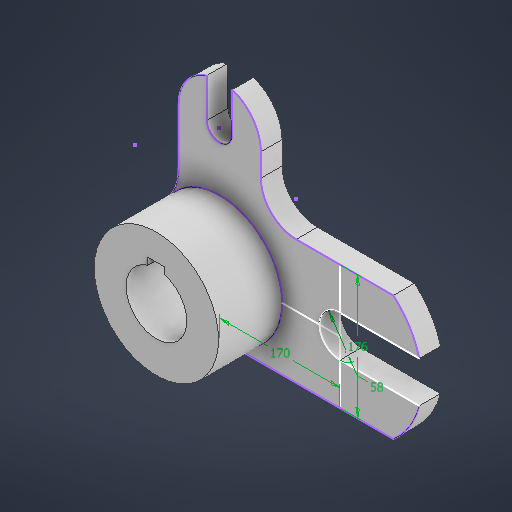
# Autodesk Inventor part: Peça3
Saved by Autodesk Inventor 2026.2 (Build 302298000, 298)
## iProperties
Created: 2026-07-31
Part Number: Peça3
Material: Genérico
Document SubType Name: Modeling
Designer: IFSP
Density: 1 g/cm^3
Appearance: Padrão
Author: IFSP
Autodesk Inventor part; units mm, degrees
ref_plane "YZ Plane" through (0, 0, 0) normal (1, 0, 0) x (0, 1, 0)
ref_plane "XZ Plane" through (0, 0, 0) normal (0, 1, 0) x (-1, 0, 0)
ref_plane "XY Plane" through (0, 0, 0) normal (0, 0, 1) x (1, 0, 0)
sketch "Esboço1" plane through (0, 0, 0) normal (0, 0, 1) x (1, 0, 0)
  circle A0 centre (0, 0) radius 88
  arc A1 (-12, 41.2916) -> (12, 41.2916) centre (0, 0) ccw
  line L0 (0, 51) -> (12, 51)
  line L1 (12, 51) -> (12, 41.2916)
  line L2 (0, 51) -> (-12, 51)
  line L3 (-12, 51) -> (-12, 41.2916)
  line L4 (0, 0) -> (170, 0)
  line L5 (-58.6335, 170.4696) -> (-58.6335, 86.4761)
  line L6 (58, 170.4696) -> (58, 138)
  arc A2 (-18.6335, 170.4696) -> (17.3665, 170.4696) centre (-0.6335, 170.4696) ccw
  line L7 (-18.6335, 170.4696) -> (-18.6335, 225.6058)
  line L8 (17.3665, 170.4696) -> (17.3665, 226.2719)
  line L9 (0, -88) -> (170, -88)
  line L10 (170, -88) -> (170, 88)
  line L11 (170, 88) -> (245.5778, 88)
  line L12 (170, -88) -> (245.5778, -88)
  arc A3 (170, 29) -> (170, -29) centre (170, 0) ccw
  line L13 (170, 29) -> (282.3165, 29)
  line L14 (170, -29) -> (282.3165, -29)
  arc A4 (-18.6335, 225.6058) -> (-58.6335, 170.4696) centre (-0.6335, 170.4696) ccw
  arc A5 (58, 170.4696) -> (17.3665, 226.2719) centre (-0.6335, 170.4696) ccw
  line L15 (170, 88) -> (108, 88)
  arc A6 (245.5778, -88) -> (282.3165, -29) centre (170, 0) ccw
  arc A7 (282.3165, 29) -> (245.5778, 88) centre (170, 0) ccw
  arc A8 (58, 138) -> (108, 88) centre (108, 138) ccw
  arc A9 (-70.6953, 52.4039) -> (-58.6335, 91.724) centre (-120.2002, 89.1001) ccw
  point P0 (58, 66.1816)
  dimension "d14" = 170
  dimension "d15" = 176
  dimension "d17" = 58
  constraints: 32 end point, 22 point on circle, 10 centre point, 10 tangent, 6 horizontal, 5 coincident, 4 perpendicular, 4 point on line, 4 vertical
  measures "d14" distance of L9.start L9.end
  measures "d15" distance of L9.end L10.end
  measures "d17" diameter of A3
extrude "Extrusão2" add sketch "Esboço1" against normal blind 30 contours A0 | L4 A3 L10 L9 A0 | A0 A9 L5 A4 L7 A2 L8 A5 L6 A8 L15 L10 A3 L4 | L10 L14 A6 L12 | L10 L11 A7 L13
extrude "Extrusão3" add sketch "Esboço1" along normal blind 90 contours A0
